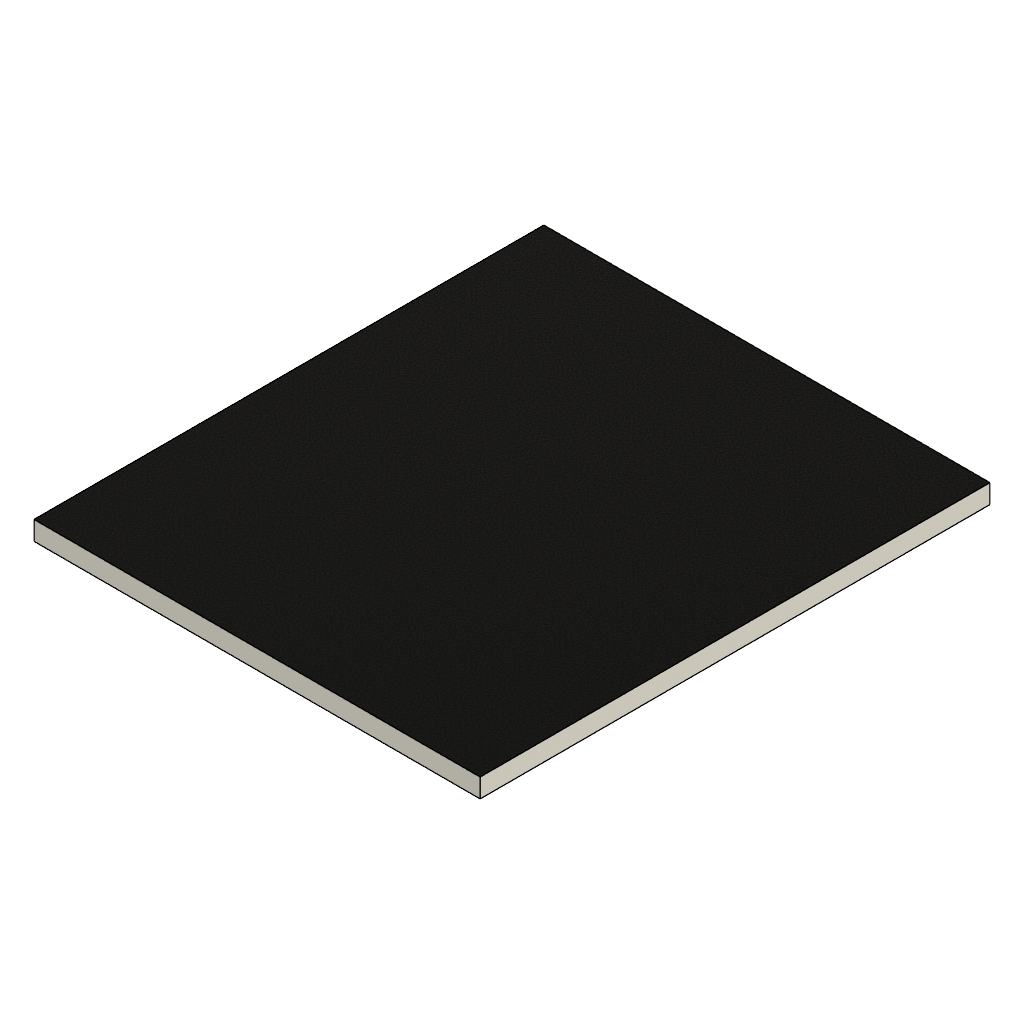
FLT CTL PNL (Autodesk Fusion 360 design; units mm, degrees)
part number: 2026-10-24-19-53-08-530
Autodesk Fusion 360 part; units mm, degrees
sketch "Sketch1" plane through (0, 0, 0) normal (0, 0, 1) x (1, 0, 0)
  line L0 (-35, 40) -> (35, 40)
  line L1 (35, 40) -> (35, -40)
  line L2 (35, -40) -> (-35, -40)
  line L3 (-35, -40) -> (-35, 40)
  circle A0 centre (27, -36) radius 2
  circle A1 centre (-27, -36) radius 2
  circle A2 centre (-27, 36) radius 2
  circle A3 centre (27, 36) radius 2
  circle A4 centre (-21.1685, -13.8269) radius 3.25
  circle A5 centre (0.4319, -0.7271) radius 3.25
  circle A6 centre (-21.2291, 13.0603) radius 3.25
  circle A7 centre (21.3669, -18.7507) radius 3.25
  circle A8 centre (21.2919, 3.9899) radius 3.25
  circle A9 centre (21.4421, 25.1902) radius 3.25
  circle A10 centre (-21.4397, -27.337) radius 1.75
  circle A11 centre (-21.4232, 26.7148) radius 1.75
  circle A12 centre (8.4947, 26.6948) radius 1.75
  circle A13 centre (8.5977, -24.7207) radius 1.75
  dimension "d1" = 80
  dimension "d2" = 70
  dimension "d3" = 40
  dimension "d4" = 35
  dimension "d5" = 4
  dimension "d6" = 4
  dimension "d7" = 8
  dimension "d8" = 4
  dimension "d9" = 8
  dimension "d10" = 4
  dimension "d11" = 4
  dimension "d12" = 4
  dimension "d13" = 8
  dimension "d14" = 4
  dimension "d15" = 8
  dimension "d16" = 4
  dimension "d17" = 6.5
  dimension "d18" = 6.5
  dimension "d19" = 6.5
  dimension "d20" = 6.5
  dimension "d21" = 6.5
  dimension "d22" = 6.5
  dimension "d23" = 3.5
  dimension "d24" = 3.5
  dimension "d25" = 3.5
  dimension "d26" = 3.5
  constraint horizontal L0
  constraint vertical L1
  constraint horizontal L2
  constraint vertical L3
  measures "d1" distance of L0.end L1.end
  measures "d2" distance of L1.end L2.end
  measures "d3" distance of origin L2
  measures "d4" distance of origin L1
  measures "d5" diameter of A0
  measures "d6" distance of L2 A0.centre
  measures "d7" distance of L1 A0.centre
  measures "d8" diameter of A1
  measures "d9" distance of L3 A1.centre
  measures "d10" distance of L2 A1.centre
  measures "d11" diameter of A2
  measures "d12" distance of L0 A2.centre
  measures "d13" distance of L3 A2.centre
  measures "d14" diameter of A3
  measures "d15" distance of L1 A3.centre
  measures "d16" distance of L0 A3.centre
  measures "d17" diameter of A4
  measures "d18" diameter of A5
  measures "d19" diameter of A6
  measures "d20" diameter of A7
  measures "d21" diameter of A8
  measures "d22" diameter of A9
  measures "d23" diameter of A10
  measures "d24" diameter of A11
  measures "d25" diameter of A12
  measures "d26" diameter of A13
sketch "Sketch2" plane through (0, 0, 0) normal (0, 0, 1) x (1, 0, 0)
  line L0 (-29.3837, -17.4764) -> (-29.3837, -9.7836) construction
  line L1 (-29.3837, -9.7836) -> (-31.5354, -9.7836) construction
  line L2 (-31.5354, -9.7836) -> (-31.5354, -17.4764) construction
  line L3 (-31.5354, -17.4764) -> (-29.3837, -17.4764) construction
  line L4 (-26.3283, -17.6237) -> (-26.3283, -9.6969) construction
  line L5 (-26.3283, -9.6969) -> (-28.4193, -9.6969) construction
  line L6 (-28.4193, -9.6969) -> (-28.4193, -17.6237) construction
  line L7 (-28.4193, -17.6237) -> (-26.3283, -17.6237) construction
  line L8 (-13.0434, -15.8642) -> (-13.0434, -11.6607) construction
  line L9 (-13.0434, -11.6607) -> (-15.0388, -11.6607) construction
  line L10 (-15.0388, -11.6607) -> (-15.0388, -15.8642) construction
  line L11 (-15.0388, -15.8642) -> (-13.0434, -15.8642) construction
  line L12 (-29.2108, 7.6119) -> (-29.2108, 18.6054) construction
  line L13 (-29.2108, 18.6054) -> (-31.6471, 18.6054) construction
  line L14 (-31.6471, 18.6054) -> (-31.6471, 7.6119) construction
  line L15 (-31.6471, 7.6119) -> (-29.2108, 7.6119) construction
  line L16 (-26.2712, 9.6858) -> (-26.2712, 17.1356) construction
  line L17 (-26.2712, 17.1356) -> (-28.3249, 17.1356) construction
  line L18 (-28.3249, 17.1356) -> (-28.3249, 9.6858) construction
  line L19 (-28.3249, 9.6858) -> (-26.2712, 9.6858) construction
  line L20 (-13.0525, 10.0787) -> (-13.0525, 16.0787) construction
  line L21 (-13.0525, 16.0787) -> (-15.0525, 16.0787) construction
  line L22 (-15.0525, 16.0787) -> (-15.0525, 10.0787) construction
  line L23 (-15.0525, 10.0787) -> (-13.0525, 10.0787) construction
  line L24 (-10.7637, -6.8591) -> (-10.7637, 5.8854) construction
  line L25 (-10.7637, 5.8854) -> (-13.149, 5.8854) construction
  line L26 (-13.149, 5.8854) -> (-13.149, -6.8591) construction
  line L27 (-13.149, -6.8591) -> (-10.7637, -6.8591) construction
  line L28 (-7.949, -3.7263) -> (-7.949, 2.4446) construction
  line L29 (-7.949, 2.4446) -> (-10.2736, 2.4446) construction
  line L30 (-10.2736, 2.4446) -> (-10.2736, -3.7263) construction
  line L31 (-10.2736, -3.7263) -> (-7.949, -3.7263) construction
  line L32 (-4.9366, -4.9309) -> (-4.9366, 3.8521) construction
  line L33 (-4.9366, 3.8521) -> (-6.8289, 3.8521) construction
  line L34 (-6.8289, 3.8521) -> (-6.8289, -4.9309) construction
  line L35 (-6.8289, -4.9309) -> (-4.9366, -4.9309) construction
  line L36 (7.7698, -4.3038) -> (7.7698, 3.4324) construction
  line L37 (7.7698, 3.4324) -> (5.8046, 3.4324) construction
  line L38 (5.8046, 3.4324) -> (5.8046, -4.3038) construction
  line L39 (5.8046, -4.3038) -> (7.7698, -4.3038) construction
  line L40 (14.0727, 1.4767) -> (14.0727, 6.6114) construction
  line L41 (14.0727, 6.6114) -> (11.7697, 6.6114) construction
  line L42 (11.7697, 6.6114) -> (11.7697, 1.4767) construction
  line L43 (11.7697, 1.4767) -> (14.0727, 1.4767) construction
  line L44 (16.6778, 0.8306) -> (16.6778, 7.4376) construction
  line L45 (16.6778, 7.4376) -> (14.7523, 7.4376) construction
  line L46 (14.7523, 7.4376) -> (14.7523, 0.8306) construction
  line L47 (14.7523, 0.8306) -> (16.6778, 0.8306) construction
  line L48 (29, 2) -> (29, 6) construction
  line L49 (29, 6) -> (27, 6) construction
  line L50 (27, 6) -> (27, 2) construction
  line L51 (27, 2) -> (29, 2) construction
  line L52 (14, -24.2622) -> (14, -12.2622) construction
  line L53 (14, -12.2622) -> (12, -12.2622) construction
  line L54 (12, -12.2622) -> (12, -24.2622) construction
  line L55 (12, -24.2622) -> (14, -24.2622) construction
  line L56 (16.689, -21.5234) -> (16.689, -15.8131) construction
  line L57 (16.689, -15.8131) -> (14.9118, -15.8131) construction
  line L58 (14.9118, -15.8131) -> (14.9118, -21.5234) construction
  line L59 (14.9118, -21.5234) -> (16.689, -21.5234) construction
  line L60 (28.6784, -21.5284) -> (28.6784, -16.0123) construction
  line L61 (28.6784, -16.0123) -> (26.7971, -16.0123) construction
  line L62 (26.7971, -16.0123) -> (26.7971, -21.5284) construction
  line L63 (26.7971, -21.5284) -> (28.6784, -21.5284) construction
  line L64 (16.6408, 23.356) -> (16.6408, 26.6771) construction
  line L65 (16.6408, 26.6771) -> (14.7919, 26.6771) construction
  line L66 (14.7919, 26.6771) -> (14.7919, 23.356) construction
  line L67 (14.7919, 23.356) -> (16.6408, 23.356) construction
  line L68 (28.8297, 23) -> (28.8297, 27.3619) construction
  line L69 (28.8297, 27.3619) -> (27, 27.3619) construction
  line L70 (27, 27.3619) -> (27, 23) construction
  line L71 (27, 23) -> (28.8297, 23) construction
  line L72 (-1.1047, 17.5) -> (-1.1047, 21.6565) construction
  line L73 (-1.1047, 21.6565) -> (-3, 21.6565) construction
  line L74 (-3, 21.6565) -> (-3, 17.5) construction
  line L75 (-3, 17.5) -> (-1.1047, 17.5) construction
  line L76 (3.2878, 18) -> (3.2878, 21.8093) construction
  line L77 (3.2878, 21.8093) -> (1, 21.8093) construction
  line L78 (1, 21.8093) -> (1, 18) construction
  line L79 (1, 18) -> (3.2878, 18) construction
  line L80 (-0.188, 14.4375) -> (0, 14.4375)
  line L81 (0, 14.4375) -> (0, 24.5)
  line L82 (0, 24.5) -> (-0.188, 24.5)
  line L83 (-0.188, 24.5) -> (-0.188, 14.4375)
  line L84 (-3.3, -24) -> (-3, -24)
  line L85 (-3, -24) -> (-3, -22.4)
  line L86 (-3, -22.4) -> (-3.3, -22.4)
  line L87 (-3.3, -22.4) -> (-3.3, -24)
  line L88 (-3.9, -23.3) -> (-2.3, -23.3)
  line L89 (-2.3, -23.3) -> (-2.3, -23)
  line L90 (-2.3, -23) -> (-3.9, -23)
  line L91 (-3.9, -23) -> (-3.9, -23.3)
  line L92 (-7.9324, -37.5173) -> (-7.9324, -35.029) construction
  line L93 (-7.9324, -35.029) -> (-19.0388, -35.029) construction
  line L94 (-19.0388, -35.029) -> (-19.0388, -37.5173) construction
  line L95 (-19.0388, -37.5173) -> (-7.9324, -37.5173) construction
  line L96 (18.5616, -37.637) -> (18.5616, -35) construction
  line L97 (18.5616, -35) -> (-6.0301, -35) construction
  line L98 (-6.0301, -35) -> (-6.0301, -37.637) construction
  line L99 (-6.0301, -37.637) -> (18.5616, -37.637) construction
  dimension "d27" = 1.5
  dimension "d29" = 1.5
  dimension "d31" = 1.5
  dimension "d33" = 1.4
  dimension "d35" = 1.4
  dimension "d37" = 1.5
  dimension "d39" = 1.5
  dimension "d41" = 1.7
  dimension "d43" = 1.7
  dimension "d45" = 1.7
  dimension "d47" = 1.7
  dimension "d49" = 1.7
  dimension "d51" = 1.7
  dimension "d53" = 1.7
  dimension "d55" = 1.7
  dimension "d57" = 1.7
  dimension "d59" = 1.7
  dimension "d61" = 1.7
  dimension "d63" = 1.7
  dimension "d65" = 1.7
  dimension "d67" = 2.7
  dimension "d69" = 3
  constraint horizontal L80
  constraint vertical L81
  constraint horizontal L82
  constraint vertical L83
  constraint horizontal L84
  constraint vertical L85
  constraint horizontal L86
  constraint vertical L87
  constraint horizontal L88
  constraint vertical L89
  constraint horizontal L90
  constraint vertical L91
extrude "Extrude9" add sketch "Sketch1" against normal blind 3 contours L0 L1 L2 L3 | A0 | A1 | A2 | A3 | A4 | A5 | A6 | A7 | A8 | A9 | A10 | A11 | A12 | A13
equation "d28 = 'DIGITAL'"
equation "d30 = 'BACKUP'"
equation "d32 = 'OFF'"
equation "d34 = 'ALT FLAPS'"
equation "d36 = 'EXTEND'"
equation "d38 = 'NORM'"
equation "d40 = 'MANUAL TF'"
equation "d42 = 'FLYUP'"
equation "d44 = 'DISABLE'"
equation "d46 = 'ENABLE'"
equation "d48 = 'FLCS'"
equation "d50 = 'RESET'"
equation "d52 = 'OFF'"
equation "d54 = 'LE FLAPS'"
equation "d56 = 'LOCK'"
equation "d58 = 'AUTO'"
equation "d60 = 'BIT'"
equation "d62 = 'OFF'"
equation "d64 = 'RUN'"
equation "d66 = 'FAIL'"
equation "d68 = 'F L T'"
equation "d70 = 'C O N T R O L'"
